Autodesk Fusion 360 part; units mm, degrees
(part 2 of 2)
equation "d797 = -pb_cy + perfboard_ancho / 2"
equation "d798 = -( perfboard_espesor )"
equation "d800 = -( rejilla_espesor + piso + poste_alto + perfboard_espesor )"
equation "d802 = perfboard_largo"
equation "d803 = perfboard_ancho"
equation "d804 = -pb_cx + perfboard_largo / 2"
equation "d805 = -pb_cy + perfboard_ancho / 2"
equation "d806 = -( altura_conjunto_montado - perfboard_espesor )"
equation "d808 = modulo_sensor_largo"
equation "d809 = modulo_sensor_ancho"
equation "d810 = -sensor_x0"
equation "d811 = modulo_y0"
equation "d812 = -( modulo_sensor_alto )"
equation "d814 = -( rejilla_espesor + caja_alto_total )"
equation "d816 = powerbank_largo"
equation "d817 = powerbank_ancho"
equation "d818 = cavidad_largo / 2 - holgura_interna"
equation "d819 = powerbank_ancho / 2"
equation "d820 = powerbank_alto"
equation "d822 = collar_x"
named bodies: "Caja_cuerpo", "Rejilla", "Sonda", "Sonda_cara_emisora", "Cono_vision_50deg", "Tapa_cuerpo", "Barra_cuerpo_1", "Barra_cuerpo_2", "Perfboard", "Componentes_volumen", "Modulo_sensor", "Powerbank"
